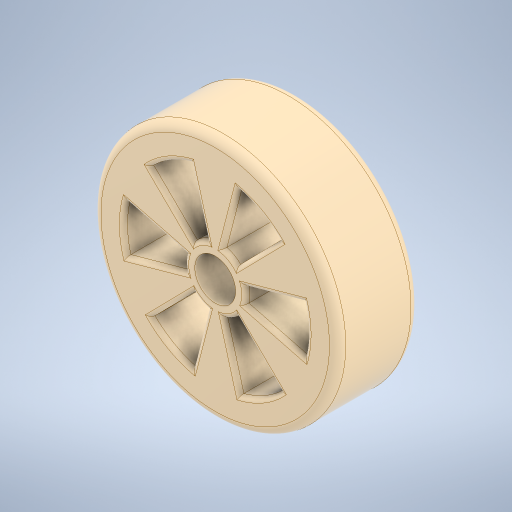
# Autodesk Inventor part: FINAL WHEEL 235
Saved by Autodesk Inventor 2023 (Build 270158000, 158)
## iProperties
Created: 2024-03-25
Part Number: FINAL WHEEL 235
Material: Polyethylene, Low Density
Document SubType Name: Modeling
Designer: stirl
Density: 0.894 g/cm^3
Appearance: Smooth - Off-White
Mass: 36.1173 g
Surface Area: 134.115 cm^2
Volume: 40.3997 cm^3
Author: stirl
Autodesk Inventor part; units mm, degrees
ref_plane "YZ Plane" through (0, 0, 0) normal (1, 0, 0) x (0, 1, 0)
ref_plane "XZ Plane" through (0, 0, 0) normal (0, 1, 0) x (-1, 0, 0)
ref_plane "XY Plane" through (0, 0, 0) normal (0, 0, 1) x (1, 0, 0)
sketch "Sketch1" plane through (0, 0, 0) normal (0, 0, 1) x (1, 0, 0)
  circle A0 centre (0, 0) radius 30
  circle A1 centre (0, 0) radius 5
  line L0 (0, 0) -> (11.3727, 27.7608)
  line L1 (0, 0) -> (23.7294, 18.3552)
  dimension "d0" = 60
  dimension "d1" = 10
  dimension "d2" = 30
  constraints: 4 end point, 2 centre point, 2 coincident, 2 point on circle
  measures "d0" diameter of A0
  measures "d1" diameter of A1
  measures "d2" angle of L1 L0
extrude "Extrusion1" add sketch "Sketch1" along normal blind 20
fillet "Fillet1" radius 2 1 edges at (-30, 0, 20)
fillet "Fillet2" radius 2 1 edges at (-30, 0, 0)
sketch "Sketch2" plane through (0, 0, 20) normal (0, 0, 1) x (1, 0, 0)
  circle A0 centre (0, 0) radius 7.5
  circle A1 centre (0, 0) radius 22.5
  line L0 (0, 0) -> (5.6144, 21.7883)
  line L1 (0, 0) -> (15.7563, 16.062)
  point P0 (5.2521, 5.354)
  point P1 (1.8715, 7.2628)
  dimension "d7" = 15
  dimension "d8" = 45
  dimension "d9" = 30
  constraints: 4 end point, 2 centre point, 2 coincident, 2 point on circle
  measures "d7" diameter of A0
  measures "d8" diameter of A1
  measures "d9" angle of L1 L0
extrude "Extrusion2" cut sketch "Sketch2" against normal blind 30 contours A0 L0 A1 L1 picked at (5.5995, 16.5111)
fillet "Fillet3" radius 1 8 edges at (3.7429, 14.5255, 20) (11.0623, 19.5927, 20) (10.5042, 10.708, 20) (3.6874, 6.5309, 20) (11.0623, 19.5927, 0) (3.7429, 14.5255, 0) (3.6874, 6.5309, 0) (10.5042, 10.708, 0)
pattern_circular "Circular Pattern1" count 6 over 360 about axis through (0, 0, 0) along (0, 0, 1) of "Fillet3", "Extrusion2"
sketch "Sketch3" plane through (0, 0, 20) normal (0, 0, 1) x (1, 0, 0)
  circle A0 centre (0, 0) radius 5
  dimension "d16" = 10
  constraints: 1 centre point, 1 coincident
  measures "d16" diameter of A0
extrude "Extrusion3" cut sketch "Sketch3" against normal blind 30
body "Solid1"
